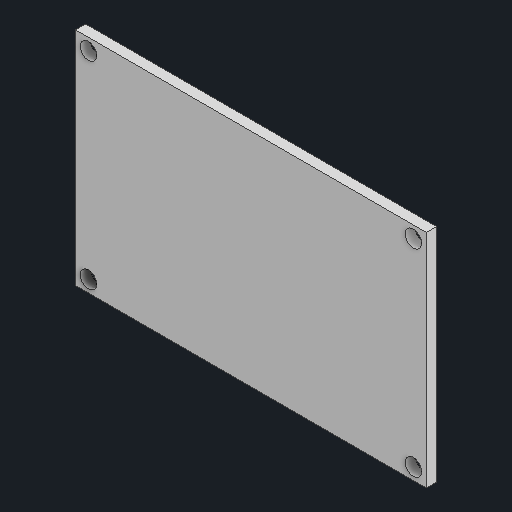
# Autodesk Inventor part: tft_1.8in_pcb
Saved by Autodesk Inventor 2027.1 (Build 311270010, 270A)
## iProperties
Created: 2026-10-29
Part Number: tft_1.8in_pcb
Material: Generic
Document SubType Name: Modeling
Designer: alexg
Density: 1 g/cm^3
Appearance: Default
Author: alexg
Autodesk Inventor part; units mm, degrees
ref_plane "YZ Plane" through (0, 0, 0) normal (1, 0, 0) x (0, 1, 0)
ref_plane "Work Plane1" through (0, 0, 25.4) normal (0, 0, 1) x (1, 0, 0)
sketch "PCB sketch" plane through (0, 0, 25.4) normal (0, 0, 1) x (1, 0, 0)
  line L0 (-28.97, 25.15) -> (26.03, 25.15)
  line L1 (26.03, 25.15) -> (26.03, 59.85)
  line L2 (26.03, 59.85) -> (-28.97, 59.85)
  line L3 (-28.97, 59.85) -> (-28.97, 25.15)
  constraints: 8 end point, 2 parallel, 1 horizontal, 1 perpendicular
extrude "PCB" add sketch "PCB sketch" against normal blind 1.6
ref_plane "Work Plane2" through (0, 0, 25.4) normal (0, 0, 1) x (1, 0, 0)
sketch "Mounting holes sketch" plane through (0, 0, 25.4) normal (0, 0, 1) x (1, 0, 0)
  circle A0 centre (-26.935, 27) radius 1.3
  circle A1 centre (23.995, 27) radius 1.3
  circle A2 centre (-26.935, 58) radius 1.3
  circle A3 centre (23.995, 58) radius 1.3
  constraints: 4 centre point
extrude "Mounting holes" cut sketch "Mounting holes sketch" against normal blind 1.6
body "Solid1"
